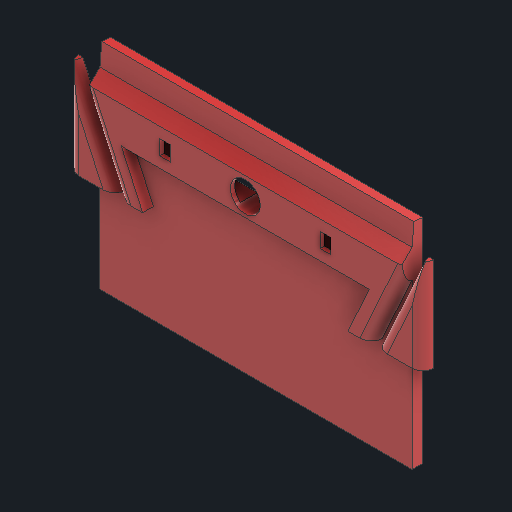
# Autodesk Inventor part: 7_3_1_avant_base
Saved by Autodesk Inventor 2026 (Build 300175000, 175)
## iProperties
Created: 2025-06-21
Part Number: 7_3_1_avant_base
Material: Generic
Document SubType Name: Modeling
Designer: remg9
Density: 1 g/cm^3
Appearance: Default
Author: remg9
Autodesk Inventor part; units mm, degrees
ref_plane "YZ Plane" through (0, 0, 0) normal (1, 0, 0) x (0, 1, 0)
ref_plane "XZ Plane" through (0, 0, 0) normal (0, 1, 0) x (-1, 0, 0)
ref_plane "XY Plane" through (0, 0, 0) normal (0, 0, 1) x (1, 0, 0)
sketch "Sketch1" plane through (0, 0, 0) normal (0, 0, 1) x (1, 0, 0)
  line L0 (0, 0) -> (146, 0)
  line L1 (146, 0) -> (146, 90)
  line L2 (146, 90) -> (0, 90)
  line L3 (0, 90) -> (0, 0)
  dimension "d0" = 90
  dimension "d1" = 146
  constraints: 8 end point, 2 parallel, 1 horizontal, 1 perpendicular
  measures "d0" distance of L0.end L1.end
  measures "d1" distance of L1.end L2.end
extrude "Extrusion1" add sketch "Sketch1" along normal blind 5
sketch "Sketch5" plane through (0, 0, 5) normal (0, 0, 1) x (1, 0, 0)
  line L0 (-10, 90) -> (156, 90)
  line L1 (156, 90) -> (156, 46)
  line L2 (156, 46) -> (121, 46)
  line L3 (121, 46) -> (131, 68)
  line L4 (131, 68) -> (15, 68)
  line L5 (15, 68) -> (25, 46)
  line L6 (25, 46) -> (-10, 46)
  line L7 (-10, 46) -> (-10, 90)
  line L8 (146, 90) -> (0, 90) projected
  line L9 (146, 0) -> (146, 90) projected
  line L10 (0, 90) -> (0, 0) projected
  point P0 (-10, 68)
  dimension "d22" = 22
  dimension "d27" = 22
  dimension "d34" = 25
  dimension "d35" = 15
  dimension "d36" = 15
  dimension "d37" = 25
  dimension "d38" = 10
  dimension "d39" = 10
  constraints: 16 end point, 3 perpendicular, 2 point on line, 1 collinear, 1 horizontal, 1 midpoint, 1 parallel
  measures "d22" distance between parallel lines of L0 L4
  measures "d27" distance between parallel lines of L4 L6
  measures "d34" distance from line of L9 L2.end
  measures "d35" distance from line of L9 L3.end
  measures "d36" distance from line of L10 L4.end
  measures "d37" distance from line of L10 L5.end
  measures "d38" distance between parallel lines of L7 L10
  measures "d39" distance between parallel lines of L9 L1
extrude "Extrusion5" add sketch "Sketch5" along normal blind 5
sketch "Sketch8" plane through (0, 0, 10) normal (0, 0, 1) x (1, 0, 0)
  line L0 (132, 46) -> (146, 76.8)
  line L1 (146, 90) -> (154, 90)
  line L2 (154, 90) -> (134, 46)
  line L3 (134, 46) -> (132, 46)
  line L4 (156, 90) -> (-10, 90) projected
  line L5 (121, 46) -> (156, 46) construction
  line L6 (131, 68) -> (121, 46) construction
  line L7 (73, 90) -> (73, 25.0765) construction
  line L8 (146, 90) -> (146, 76.8)
  line L9 (14, 46) -> (0, 76.8)
  line L10 (0, 90) -> (-8, 90)
  line L11 (-8, 90) -> (12, 46)
  line L12 (12, 46) -> (14, 46)
  line L13 (25, 46) -> (-10, 46) construction
  line L14 (15, 68) -> (25, 46) construction
  line L15 (0, 90) -> (0, 76.8)
  point P0 (0, 0)
  dimension "d40" = 8
  dimension "d41" = 2
  dimension "d49" = 2
  constraints: 26 end point, 8 symmetric about line, 3 parallel, 2 collinear, 2 vertical, 1 horizontal, 1 midpoint
  measures "d40" distance of L1.start L1.end
  measures "d41" distance of L4.start L1.end
  measures "d49" distance of L2.end L0.start
extrude "Extrusion7" cut sketch "Sketch8" against normal blind 5
fillet "Fillet1" radius 5 4 edges at (156, 68, 10) (-10, 68, 10) (144, 68, 10) (2, 68, 10)
fillet "Fillet2" radius 5 2 edges at (139, 61.4, 10) (7, 61.4, 10)
sketch "Sketch10" plane through (146, 0, 0) normal (1, 0, 0) x (0, 0, -1)
  line L0 (0, 90) -> (0, 99.6008)
  line L1 (0, 99.6008) -> (-4.1284, 99.9619)
  line L2 (-4.1284, 99.9619) -> (-5, 90)
  line L3 (-5, 90) -> (0, 90)
  line L4 (0, 0) -> (0, 90) projected
  line L5 (0, 90) -> (-10, 90) projected
  line L6 (-4.1284, 99.9619) -> (5.6002, 99.9619) construction
  line L7 (-5, 90) -> (-5, 102.7546) construction
  dimension "d50" = 5
  dimension "d51" = 5
  dimension "d54" = 10
  dimension "d56" = 5
  constraints: 12 end point, 2 collinear, 2 vertical, 1 horizontal, 1 perpendicular
  measures "d50" angle of L7 L2
  measures "d51" angle of L1 L6
  measures "d54" distance from line of L1 L2.end
  measures "d56" distance of L2.end L0.start
extrude "Extrusion8" add sketch "Sketch10" against normal blind 146
chamfer "Chamfer2" distance 5 angle 45 1 edges at (73, 90, 10)
sketch "Sketch11" plane through (0, 0, 10) normal (0, 0, 1) x (1, 0, 0)
  line L0 (73, 85) -> (73, 68) construction
  line L1 (10.8593, 76.5) -> (129.6871, 76.5) construction
  line L2 (1.765, 85) -> (144.235, 85) projected
  line L3 (15, 68) -> (131, 68) projected
  line L4 (33, 80) -> (38, 80)
  line L5 (38, 80) -> (38, 73)
  line L6 (38, 73) -> (33, 73)
  line L7 (33, 73) -> (33, 80)
  arc A0 (73, 83.5) -> (73, 69.5) centre (73, 76.5) ccw
  line L8 (113, 80) -> (108, 80)
  line L9 (108, 80) -> (108, 73)
  line L10 (108, 73) -> (113, 73)
  line L11 (113, 73) -> (113, 80)
  arc A1 (73, 69.5) -> (73, 83.5) centre (73, 76.5) ccw
  point P0 (0, 0)
  point P1 (38, 76.5)
  point P2 (135.1407, 76.5)
  point P3 (108, 76.5)
  dimension "d60" = 5
  dimension "d61" = 7
  dimension "d62" = 7
  dimension "d63" = 35
  constraints: 20 end point, 6 symmetric about line, 4 midpoint, 4 point on circle, 4 point on line, 2 centre point, 2 horizontal, 2 parallel, 1 coincident, 1 perpendicular, 1 vertical, 1 other
  measures "d60" distance of L4.start L4.end
  measures "d61" distance of L4.end L5.end
  measures "d62" radius of A0
  measures "d63" distance between parallel lines of L0 L5
extrude "Extrusion9" cut sketch "Sketch11" against normal through all
sketch "Sketch12" plane through (0, 0, 0) normal (0, 0, -1) x (-1, 0, 0)
  line L0 (-124, 82) -> (-22, 82)
  line L1 (-22, 82) -> (-22, 71)
  line L2 (-22, 71) -> (-124, 71)
  line L3 (-124, 71) -> (-124, 82)
  line L4 (-108, 76.5) -> (-38, 76.5) construction
  line L5 (-38, 73) -> (-38, 80) construction
  line L6 (-108, 80) -> (-108, 73) construction
  line L7 (-73, 82) -> (-73, 73) construction
  line L8 (-33, 80) -> (-33, 73) construction
  point P0 (0, 0)
  point P1 (-22, 76.5)
  point P2 (-73, 76.5)
  dimension "d66" = 11
  dimension "d67" = 11
  constraints: 12 end point, 5 midpoint, 2 horizontal, 2 parallel, 2 point on line, 1 perpendicular, 1 vertical
  measures "d66" distance between parallel lines of L2 L0
  measures "d67" distance between parallel lines of L1 L8
extrude "Extrusion10" cut sketch "Sketch12" against normal blind 8
body "Solid1"
